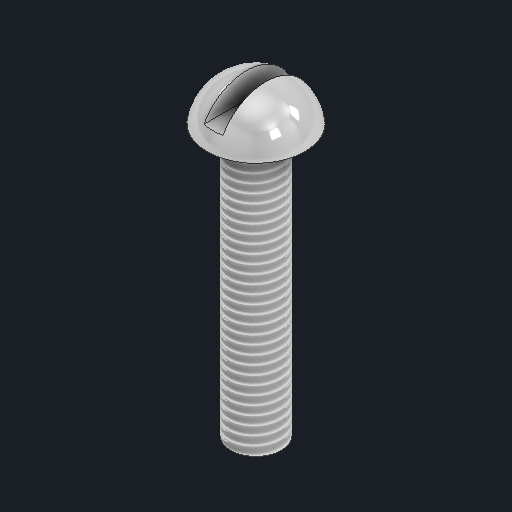
# Autodesk Inventor part: Parafuso 2,9 x 15,5mm
Saved by Autodesk Inventor 2026.1 (Build 301233000, 233)
## iProperties
Created: 2025-01-14
Part Number: Parafuso 2,9 x 15,5mm
Material: Aço
Document SubType Name: Modeling
Designer: Cliente
Density: 7.85 g/cm^3
Appearance: Placa
Mass: 1.04732 g
Surface Area: 2.17346 cm^2
Volume: 0.133417 cm^3
Author: Cliente
Autodesk Inventor part; units mm, degrees
ref_plane "YZ Plane" through (0, 0, 0) normal (1, 0, 0) x (0, 1, 0)
ref_plane "XZ Plane" through (0, 0, 0) normal (0, 1, 0) x (-1, 0, 0)
sketch "Esboço1" plane through (0, 0, 0) normal (0, 1, 0) x (-1, 0, 0)
  circle A0 centre (0, 0) radius 1.45
  dimension "d0" = 2.9
  constraints: 1 centre point, 1 coincident
  measures "d0" diameter of A0
extrude "Extrusão1" add sketch "Esboço1" against normal blind 15.5
sketch "Esboço2" plane through (0, 0, 0) normal (1, 0, 0) x (0, 1, 0)
  line L0 (0, -1.45) -> (0, 1.45) projected
  line L1 (0, 2.8) -> (0, -2.8)
  line L2 (0, 0) -> (2.4, 0)
  arc A0 (0, -2.8) -> (0, 2.8) centre (-0.4333, 0) ccw
  dimension "d3" = 5.6
  dimension "d4" = 2.4
  constraints: 4 end point, 3 point on circle, 2 midpoint, 1 centre point, 1 horizontal, 1 vertical
  measures "d3" distance of L1.start L1.end
  measures "d4" distance of L2.start L2.end
revolve "Revolução1" add sketch "Esboço2" angle 360 about axis through (0, 0, 0) along (0, 1, 0) picked at (0.6966, -0.9131) contours L0 L2 A0 L1
ref_plane "Plano de trabalho1" through (0, 2.4, 0) normal (0, -1, 0) x (1, 0, 0)
sketch "Esboço3" plane through (0, 2.4, 0) normal (0, -1, 0) x (1, 0, 0)
  line L0 (0.55, -2.8) -> (-0.55, -2.8)
  line L1 (-0.55, -2.8) -> (-0.55, 2.8)
  line L2 (-0.55, 2.8) -> (0.55, 2.8)
  line L3 (0.55, 2.8) -> (0.55, -2.8)
  line L4 (0.55, -2.8) -> (-0.55, 2.8) construction
  line L5 (-0.55, -2.8) -> (0.55, 2.8) construction
  circle A0 centre (0, 0) radius 2.8 projected
  point P0 (0.55, 2.7455)
  point P1 (-0.55, 2.7455)
  point P2 (-0.55, -2.7455)
  point P3 (0.55, -2.7455)
  dimension "d6" = 1.1
  constraints: 12 end point, 2 midpoint, 2 parallel, 1 horizontal, 1 perpendicular, 1 tangent
  measures "d6" distance of L1.end L2.end
extrude "Extrusão2" cut sketch "Esboço3" along normal blind 1.5 contours A0 L1 L3
thread "Rosca1" size "M3x0.5" class "6g" standard "ANSI Metric M Profile" length 20
